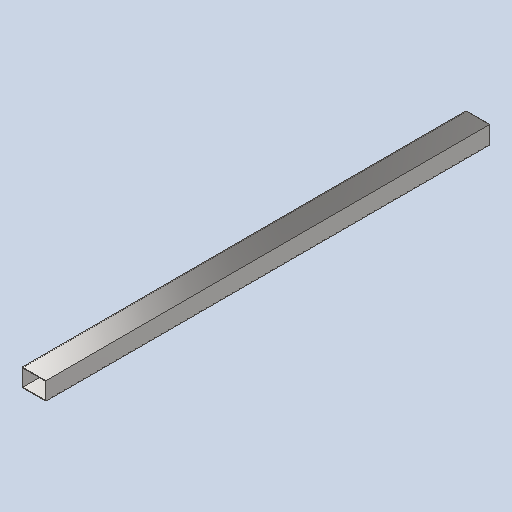
# Autodesk Inventor part: RDS-2201 Tube 80x60 L1500
Saved by Autodesk Inventor 2026.2 (Build 302298000, 298)
## iProperties
Created: 2026-10-18
Part Number: RDS-2201 Tube 80x60 L1500
Material: Stainless Steel, Austenitic
Description: Platform rail, AISI 304
Document SubType Name: Modeling
Designer: admin
Stock Number: Труба 80х60х2 L1500 — продольная площадки (×2)
Density: 8 g/cm^3
Appearance: Semi-Polished
Author: admin
Autodesk Inventor part; units mm, degrees
ref_plane "YZ Plane" through (0, 0, 0) normal (1, 0, 0) x (0, 1, 0)
ref_plane "XZ Plane" through (0, 0, 0) normal (0, 1, 0) x (-1, 0, 0)
ref_plane "XY Plane" through (0, 0, 0) normal (0, 0, 1) x (1, 0, 0)
sketch "Sketch1" plane through (0, 0, 0) normal (0, 0, 1) x (1, 0, 0)
  line L0 (-40, -30) -> (40, -30)
  line L1 (40, -30) -> (40, 30)
  line L2 (40, 30) -> (-40, 30)
  line L3 (-40, 30) -> (-40, -30)
  line L4 (-38, -28) -> (38, -28)
  line L5 (38, -28) -> (38, 28)
  line L6 (38, 28) -> (-38, 28)
  line L7 (-38, 28) -> (-38, -28)
  constraints: 16 end point, 4 parallel, 2 horizontal, 2 perpendicular
extrude "Extrusion1" add sketch "Sketch1" along normal blind 1500
equation "\"d0\" = Tube2201_Length"
equation "\"Tube2201_Length\" = 1500"
equation "\"Tube2201_Wall_Thickness\" = 2"
body "Solid1"
